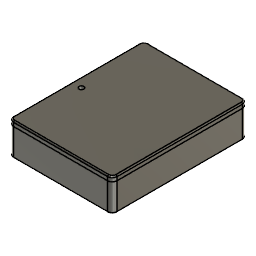
Power_Bank- (Autodesk Fusion 360 design; units mm, degrees)
part number: 2026-11-16-17-15-26-858
part number: 2026-11-16-17-44-09-505
part number: 2026-11-16-20-38-29-058
Autodesk Fusion 360 part; units mm, degrees
sketch "Outer_Profile" plane through (0, 0, 0) normal (0, 0, 1) x (1, 0, 0) in component "Case_Base"
  arc A0 (21.7, 26.3) -> (19.7, 28.3) centre (19.7, 26.3) ccw
  line L0 (19.7, 28.3) -> (-19.7, 28.3)
  arc A1 (-19.7, 28.3) -> (-21.7, 26.3) centre (-19.7, 26.3) ccw
  line L1 (-21.7, 26.3) -> (-21.7, -26.3)
  arc A2 (-21.7, -26.3) -> (-19.7, -28.3) centre (-19.7, -26.3) ccw
  line L2 (-19.7, -28.3) -> (19.7, -28.3)
  arc A3 (19.7, -28.3) -> (21.7, -26.3) centre (19.7, -26.3) ccw
  line L3 (21.7, -26.3) -> (21.7, 26.3)
extrude "Outer_Extrude" add sketch "Outer_Profile" along normal blind 11.7 makes body 1 in component "Case_Base"
ref_plane "WorkPlane1" through (0, 0, 2) normal (0, 0, 1) x (1, 0, 0) in component "Case_Base"
sketch "Pocket_Profile" plane through (0, 0, 2) normal (0, 0, 1) x (1, 0, 0) in component "Case_Base"
  arc A0 (19.7, 25.8) -> (19.2, 26.3) centre (19.2, 25.8) ccw
  line L0 (19.2, 26.3) -> (-19.2, 26.3)
  arc A1 (-19.2, 26.3) -> (-19.7, 25.8) centre (-19.2, 25.8) ccw
  line L1 (-19.7, 25.8) -> (-19.7, -25.8)
  arc A2 (-19.7, -25.8) -> (-19.2, -26.3) centre (-19.2, -25.8) ccw
  line L2 (-19.2, -26.3) -> (19.2, -26.3)
  arc A3 (19.2, -26.3) -> (19.7, -25.8) centre (19.2, -25.8) ccw
  line L3 (19.7, -25.8) -> (19.7, 25.8)
extrude "Pocket_Cut" cut sketch "Pocket_Profile" along normal blind 9.7 bodies 1 in component "Case_Base"
sketch "Corner_Posts_Profile" plane through (0, 0, 2) normal (0, 0, 1) x (1, 0, 0) in component "Case_Base"
  line L0 (19.7, 26.3) -> (16.7, 26.3)
  line L1 (16.7, 26.3) -> (16.7, 23.3)
  line L2 (16.7, 23.3) -> (19.7, 23.3)
  line L3 (19.7, 23.3) -> (19.7, 26.3)
  line L4 (19.7, -23.3) -> (16.7, -23.3)
  line L5 (16.7, -23.3) -> (16.7, -26.3)
  line L6 (16.7, -26.3) -> (19.7, -26.3)
  line L7 (19.7, -26.3) -> (19.7, -23.3)
  line L8 (-16.7, 26.3) -> (-19.7, 26.3)
  line L9 (-19.7, 26.3) -> (-19.7, 23.3)
  line L10 (-19.7, 23.3) -> (-16.7, 23.3)
  line L11 (-16.7, 23.3) -> (-16.7, 26.3)
  line L12 (-16.7, -23.3) -> (-19.7, -23.3)
  line L13 (-19.7, -23.3) -> (-19.7, -26.3)
  line L14 (-19.7, -26.3) -> (-16.7, -26.3)
  line L15 (-16.7, -26.3) -> (-16.7, -23.3)
extrude "Corner_Posts" add sketch "Corner_Posts_Profile" along normal blind 1.5 bodies 1 in component "Case_Base"
ref_plane "WorkPlane2" through (0, 0, 3.5) normal (0, 0, 1) x (1, 0, 0) in component "Case_Base"
sketch "PCB_Profile" plane through (0, 0, 3.5) normal (0, 0, 1) x (1, 0, 0) in component "Case_Base"
  line L0 (19.4, 26) -> (-19.4, 26)
  line L1 (-19.4, 26) -> (-19.4, -26)
  line L2 (-19.4, -26) -> (19.4, -26)
  line L3 (19.4, -26) -> (19.4, 26)
extrude "PCB_Reference_Extrude" add sketch "PCB_Profile" along normal blind 1.6 separate body makes body 2 in component "Case_Base"
ref_plane "WorkPlane3" through (0, 0, 5.1) normal (0, 0, 1) x (1, 0, 0) in component "Case_Base"
sketch "L1_Keepout_Profile" plane through (0, 0, 5.1) normal (0, 0, 1) x (1, 0, 0) in component "Case_Base"
  line L0 (-0.1, -8.3) -> (-13.1, -8.3)
  line L1 (-13.1, -8.3) -> (-13.1, -21.3)
  line L2 (-13.1, -21.3) -> (-0.1, -21.3)
  line L3 (-0.1, -21.3) -> (-0.1, -8.3)
extrude "L1_Keepout_Extrude" add sketch "L1_Keepout_Profile" along normal blind 6 separate body makes body 3 in component "Case_Base"
sketch "USBC_Counterbore_Profile" plane through (0, 28.3, 0) normal (0, 1, 0) x (-1, 0, 0) in component "Case_Base"
  line L0 (-19.7, 0) -> (19.7, 0)
  line L1 (19.7, 0) -> (19.7, 11.7)
  line L2 (19.7, 11.7) -> (-19.7, 11.7)
  line L3 (-19.7, 11.7) -> (-19.7, 0)
  line L4 (12.69, 10.03) -> (6.69, 10.03)
  arc A0 (6.69, 10.03) -> (6.69, 3.43) centre (6.69, 6.73) ccw
  line L5 (6.69, 3.43) -> (12.69, 3.43)
  arc A1 (12.69, 3.43) -> (12.69, 10.03) centre (12.69, 6.73) ccw
extrude "USBC_Counterbore" cut sketch "USBC_Counterbore_Profile" against normal blind 1.4 contours L4 A0 L5 A1 bodies 1 in component "Case_Base"
sketch "USBC_Window_Profile" plane through (0, 28.3, 0) normal (0, 1, 0) x (-1, 0, 0) in component "Case_Base"
  line L0 (6.69, 10.03) -> (12.69, 10.03)
  arc A0 (12.69, 3.43) -> (12.69, 10.03) centre (12.69, 6.73) ccw
  line L1 (12.69, 3.43) -> (6.69, 3.43)
  arc A1 (6.69, 10.03) -> (6.69, 3.43) centre (6.69, 6.73) ccw
  line L2 (-19.7, 0) -> (19.7, 0)
  line L3 (19.7, 0) -> (19.7, 11.7)
  line L4 (19.7, 11.7) -> (-19.7, 11.7)
  line L5 (-19.7, 11.7) -> (-19.7, 0)
  line L6 (12.59, 8.63) -> (6.79, 8.63)
  arc A2 (6.79, 8.63) -> (6.79, 4.83) centre (6.79, 6.73) ccw
  line L7 (6.79, 4.83) -> (12.59, 4.83)
  arc A3 (12.59, 4.83) -> (12.59, 8.63) centre (12.59, 6.73) ccw
extrude "USBC_Window" cut sketch "USBC_Window_Profile" against normal blind 2 contours L6 A2 L7 A3 bodies 1 in component "Case_Base"
chamfer "USBC_Counterbore_Chamfer" distance 0.3 angle 45 4 edges at (-9.69, 28.3, 10.03) (-15.99, 28.3, 6.73) (-9.69, 28.3, 3.43) (-3.39, 28.3, 6.73) on bodies 1 in component "Case_Base"
ref_plane "WorkPlane1" through (0, 0, 11.7) normal (0, 0, 1) x (1, 0, 0) in component "Case_Lid"
sketch "Lid_Plate_Profile" plane through (0, 0, 11.7) normal (0, 0, 1) x (1, 0, 0) in component "Case_Lid"
  arc A0 (21.7, 26.3) -> (19.7, 28.3) centre (19.7, 26.3) ccw
  line L0 (19.7, 28.3) -> (-19.7, 28.3)
  arc A1 (-19.7, 28.3) -> (-21.7, 26.3) centre (-19.7, 26.3) ccw
  line L1 (-21.7, 26.3) -> (-21.7, -26.3)
  arc A2 (-21.7, -26.3) -> (-19.7, -28.3) centre (-19.7, -26.3) ccw
  line L2 (-19.7, -28.3) -> (19.7, -28.3)
  arc A3 (19.7, -28.3) -> (21.7, -26.3) centre (19.7, -26.3) ccw
  line L3 (21.7, -26.3) -> (21.7, 26.3)
extrude "Lid_Plate" add sketch "Lid_Plate_Profile" along normal blind 2 separate body makes body 4 in component "Case_Lid"
sketch "Lid_Lip_Profile" plane through (0, 0, 11.7) normal (0, 0, 1) x (1, 0, 0) in component "Case_Lid"
  arc A0 (19.5, 25.7) -> (19.1, 26.1) centre (19.1, 25.7) ccw
  line L0 (19.1, 26.1) -> (-19.1, 26.1)
  arc A1 (-19.1, 26.1) -> (-19.5, 25.7) centre (-19.1, 25.7) ccw
  line L1 (-19.5, 25.7) -> (-19.5, -25.7)
  arc A2 (-19.5, -25.7) -> (-19.1, -26.1) centre (-19.1, -25.7) ccw
  line L2 (-19.1, -26.1) -> (19.1, -26.1)
  arc A3 (19.1, -26.1) -> (19.5, -25.7) centre (19.1, -25.7) ccw
  line L3 (19.5, -25.7) -> (19.5, 25.7)
  line L4 (-18.3, -24.9) -> (18.3, -24.9)
  line L5 (18.3, -24.9) -> (18.3, 24.9)
  line L6 (18.3, 24.9) -> (-18.3, 24.9)
  line L7 (-18.3, 24.9) -> (-18.3, -24.9)
extrude "Lid_Lip" add sketch "Lid_Lip_Profile" against normal blind 1 bodies 4 in component "Case_Lid"
sketch "Lid_Pressers_Profile" plane through (0, 0, 11.7) normal (0, 0, 1) x (1, 0, 0) in component "Case_Lid"
  line L0 (16.9, 24) -> (19.4, 24)
  line L1 (19.4, 24) -> (19.4, 26)
  line L2 (19.4, 26) -> (16.9, 26)
  line L3 (16.9, 26) -> (16.9, 24)
  line L4 (16.9, -24) -> (19.4, -24)
  line L5 (19.4, -24) -> (19.4, -26)
  line L6 (19.4, -26) -> (16.9, -26)
  line L7 (16.9, -26) -> (16.9, -24)
  line L8 (-16.9, 24) -> (-19.4, 24)
  line L9 (-19.4, 24) -> (-19.4, 26)
  line L10 (-19.4, 26) -> (-16.9, 26)
  line L11 (-16.9, 26) -> (-16.9, 24)
  line L12 (-16.9, -24) -> (-19.4, -24)
  line L13 (-19.4, -24) -> (-19.4, -26)
  line L14 (-19.4, -26) -> (-16.9, -26)
  line L15 (-16.9, -26) -> (-16.9, -24)
extrude "Lid_Pressers" add sketch "Lid_Pressers_Profile" against normal blind 6.5 bodies 4 in component "Case_Lid"
sketch "LED_Hole_Profile" plane through (0, 0, 11.7) normal (0, 0, 1) x (1, 0, 0) in component "Case_Lid"
  circle A0 centre (-17.525, -2) radius 1
extrude "LED_Hole" cut sketch "LED_Hole_Profile" along normal blind 2 bodies 4 in component "Case_Lid"
sketch "Snap_Bumps_Profile" plane through (0, 0, 0) normal (0, 1, 0) x (1, 0, 0) in component "Case_Lid"
  arc A0 (19.5, -11.6) -> (19.5, -10.8) centre (19.5, -11.2) ccw
  line L0 (19.5, -10.8) -> (19.5, -11.6)
  arc A1 (-19.5, -10.8) -> (-19.5, -11.6) centre (-19.5, -11.2) ccw
  line L1 (-19.5, -10.8) -> (-19.5, -11.6)
extrude "Snap_Bumps" add sketch "Snap_Bumps_Profile" along normal mid plane 6 bodies 4 in component "Case_Lid"
sketch "Snap_Dimples_Profile" plane through (0, 0, 0) normal (0, 1, 0) x (1, 0, 0) in component "Case_Base"
  arc A0 (19.7, -11.7) -> (19.7, -10.7) centre (19.7, -11.2) ccw
  line L0 (19.7, -10.7) -> (19.7, -11.7)
  arc A1 (-19.7, -10.7) -> (-19.7, -11.7) centre (-19.7, -11.2) ccw
  line L1 (-19.7, -10.7) -> (-19.7, -11.7)
extrude "Snap_Dimples" cut sketch "Snap_Dimples_Profile" along normal mid plane 6 bodies 1 in component "Case_Base"
fillet "Lid_Top_Fillet" radius 0.5 64 edges at (21.7, 0, 13.7) (21.1142, 27.7142, 13.7) (0, 28.3, 13.7) (-21.1142, 27.7142, 13.7) (-21.7, 0, 13.7) (-21.1142, -27.7142, 13.7) (0, -28.3, 13.7) (21.1142, -27.7142, 13.7) (21.1142, 27.7142, 13.7) (0, 28.3, 13.7) (-21.1142, 27.7142, 13.7) (-21.7, 0, 13.7) (-21.1142, -27.7142, 13.7) (0, -28.3, 13.7) (21.1142, -27.7142, 13.7) (21.7, 0, 13.7) (0, 28.3, 13.7) (-21.1142, 27.7142, 13.7) (-21.7, 0, 13.7) (-21.1142, -27.7142, 13.7) (0, -28.3, 13.7) (21.1142, -27.7142, 13.7) (21.7, 0, 13.7) (21.1142, 27.7142, 13.7) (-21.1142, 27.7142, 13.7) (-21.7, 0, 13.7) (-21.1142, -27.7142, 13.7) (0, -28.3, 13.7) (21.1142, -27.7142, 13.7) (21.7, 0, 13.7) (21.1142, 27.7142, 13.7) (0, 28.3, 13.7) (-21.7, 0, 13.7) (-21.1142, -27.7142, 13.7) (0, -28.3, 13.7) (21.1142, -27.7142, 13.7) (21.7, 0, 13.7) (21.1142, 27.7142, 13.7) (0, 28.3, 13.7) (-21.1142, 27.7142, 13.7) (-21.1142, -27.7142, 13.7) (0, -28.3, 13.7) (21.1142, -27.7142, 13.7) (21.7, 0, 13.7) (21.1142, 27.7142, 13.7) (0, 28.3, 13.7) (-21.1142, 27.7142, 13.7) (-21.7, 0, 13.7) (0, -28.3, 13.7) (21.1142, -27.7142, 13.7) (21.7, 0, 13.7) (21.1142, 27.7142, 13.7) (0, 28.3, 13.7) (-21.1142, 27.7142, 13.7) (-21.7, 0, 13.7) (-21.1142, -27.7142, 13.7) (21.1142, -27.7142, 13.7) (21.7, 0, 13.7) (21.1142, 27.7142, 13.7) (0, 28.3, 13.7) (-21.1142, 27.7142, 13.7) (-21.7, 0, 13.7) (-21.1142, -27.7142, 13.7) (0, -28.3, 13.7) on bodies 4 in component "Case_Lid"
sketch "Snap_Grooves_6p4_Profile" plane through (0, 0, 0) normal (0, 1, 0) x (1, 0, 0) in component "Case_Base"
  arc A0 (19.7, -11.7) -> (19.7, -10.7) centre (19.7, -11.2) ccw
  line L0 (19.7, -10.7) -> (19.7, -11.7)
  arc A1 (-19.7, -10.7) -> (-19.7, -11.7) centre (-19.7, -11.2) ccw
  line L1 (-19.7, -10.7) -> (-19.7, -11.7)
extrude "Snap_Grooves_6p4" cut sketch "Snap_Grooves_6p4_Profile" along normal mid plane 6.4 bodies 1 in component "Case_Base"
fillet "Base_Bottom_Fillet" radius 0.5 64 edges at (21.7, 0, 0) (21.1142, 27.7142, 0) (0, 28.3, 0) (-21.1142, 27.7142, 0) (-21.7, 0, 0) (-21.1142, -27.7142, 0) (0, -28.3, 0) (21.1142, -27.7142, 0) (21.1142, -27.7142, 0) (21.7, 0, 0) (21.1142, 27.7142, 0) (0, 28.3, 0) (-21.1142, 27.7142, 0) (-21.7, 0, 0) (-21.1142, -27.7142, 0) (0, -28.3, 0) (0, -28.3, 0) (21.1142, -27.7142, 0) (21.7, 0, 0) (21.1142, 27.7142, 0) (0, 28.3, 0) (-21.1142, 27.7142, 0) (-21.7, 0, 0) (-21.1142, -27.7142, 0) (-21.1142, -27.7142, 0) (0, -28.3, 0) (21.1142, -27.7142, 0) (21.7, 0, 0) (21.1142, 27.7142, 0) (0, 28.3, 0) (-21.1142, 27.7142, 0) (-21.7, 0, 0) (-21.7, 0, 0) (-21.1142, -27.7142, 0) (0, -28.3, 0) (21.1142, -27.7142, 0) (21.7, 0, 0) (21.1142, 27.7142, 0) (0, 28.3, 0) (-21.1142, 27.7142, 0) (-21.1142, 27.7142, 0) (-21.7, 0, 0) (-21.1142, -27.7142, 0) (0, -28.3, 0) (21.1142, -27.7142, 0) (21.7, 0, 0) (21.1142, 27.7142, 0) (0, 28.3, 0) (0, 28.3, 0) (-21.1142, 27.7142, 0) (-21.7, 0, 0) (-21.1142, -27.7142, 0) (0, -28.3, 0) (21.1142, -27.7142, 0) (21.7, 0, 0) (21.1142, 27.7142, 0) (21.1142, 27.7142, 0) (0, 28.3, 0) (-21.1142, 27.7142, 0) (-21.7, 0, 0) (-21.1142, -27.7142, 0) (0, -28.3, 0) (21.1142, -27.7142, 0) (21.7, 0, 0) on bodies 1 in component "Case_Base"
component "Case_Base" placed x (1, 0, 0) y (0, 1, 0) z (0, 0, 1) at (0, 0, 0)
component "Case_Lid" placed x (1, 0, 0) y (0, 1, 0) z (0, 0, 1) at (0, 0, 0)
hidden bodies 2 3
equation "d14 = -( 1.40 mm )"
equation "d16 = -( 2.00 mm )"
equation "d22 = -( 1.00 mm )"
equation "d24 = -( 6.50 mm )"
named bodies: "Case_Base_Body", "PCB_Reference", "L1_Keepout", "Case_Lid_Body"
